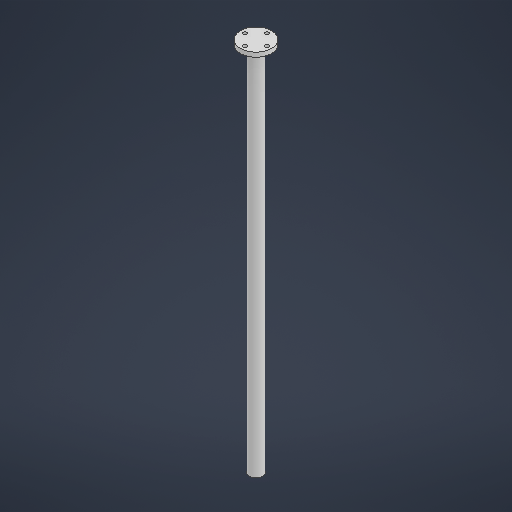
# Autodesk Inventor part: bras_intérieur_tige
Saved by Autodesk Inventor 2026.1 (Build 301233020, 233B)
## iProperties
Created: 2026-11-20
Part Number: bras_intérieur_tige
Material: Generic
Document SubType Name: Modeling
Designer: matar
Density: 1 g/cm^3
Appearance: Default
Author: matar
Autodesk Inventor part; units mm, degrees
ref_plane "YZ Plane" through (0, 0, 0) normal (1, 0, 0) x (0, 1, 0)
ref_plane "XZ Plane" through (0, 0, 0) normal (0, 1, 0) x (-1, 0, 0)
ref_plane "XY Plane" through (0, 0, 0) normal (0, 0, 1) x (1, 0, 0)
sketch "Sketch1" plane through (0, 0, 0) normal (0, 1, 0) x (-1, 0, 0)
  circle A0 centre (0, 0) radius 7.5
  dimension "d0" = 15
  constraints: 1 centre point, 1 coincident
  measures "d0" diameter of A0
extrude "Extrusion1" add sketch "Sketch1" along normal blind 400
sketch "Sketch2" plane through (0, 0, 0) normal (0, -1, 0) x (1, 0, 0)
  circle A0 centre (0, 0) radius 7.5 projected
  circle A1 centre (0, 0) radius 7.5
  line L0 (0, -4) -> (4, 0)
  arc A2 (4, 0) -> (0, -4) centre (0, 0) ccw
  constraints: 2 centre point, 2 coincident, 2 end point, 2 point on circle, 1 concentric
extrude "Extrusion2" add sketch "Sketch2" along normal blind 15
sketch "Sketch4" plane through (0, -15, 0) normal (0, -1, 0) x (1, 0, 0)
  circle A0 centre (0, 0) radius 7.5
  circle A1 centre (0, 0) radius 4
  constraints: 2 centre point, 2 coincident
extrude "Extrusion3" add sketch "Sketch4" along normal blind 6
sketch "Sketch5" plane through (0, 400, 0) normal (0, 1, 0) x (1, 0, 0)
  circle A0 centre (0, 0) radius 17.5
  dimension "d10" = 35
  constraints: 1 centre point, 1 coincident
  measures "d10" diameter of A0
extrude "Extrusion4" add sketch "Sketch5" along normal blind 5
sketch "Sketch6" plane through (0, 400, 0) normal (0, -1, 0) x (1, 0, 0)
  circle A0 centre (12.5, 0) radius 2
  circle A1 centre (0, -12.5) radius 2
  circle A2 centre (-12.5, 0) radius 2
  circle A3 centre (0, 12.5) radius 2
  circle A4 centre (0, 0) radius 17.5 projected
  circle A5 centre (0, 0) radius 7.5 projected
  dimension "d13" = 4
  dimension "d14" = 4
  dimension "d15" = 4
  dimension "d16" = 4
  dimension "d18" = 12.5
  dimension "d19" = 12.5
  dimension "d20" = 12.5
  dimension "d21" = 12.5
  constraints: 4 centre point
  measures "d13" diameter of A3
  measures "d14" diameter of A0
  measures "d15" diameter of A1
  measures "d16" diameter of A2
  measures "d18" distance of A5.centre A3.centre
  measures "d19" distance of A5.centre A0.centre
  measures "d20" distance of A5.centre A1.centre
  measures "d21" distance of A5.centre A2.centre
extrude "Extrusion5" cut sketch "Sketch6" against normal through all contours A0 | A1 | A2 | A3
body "Solid1"
